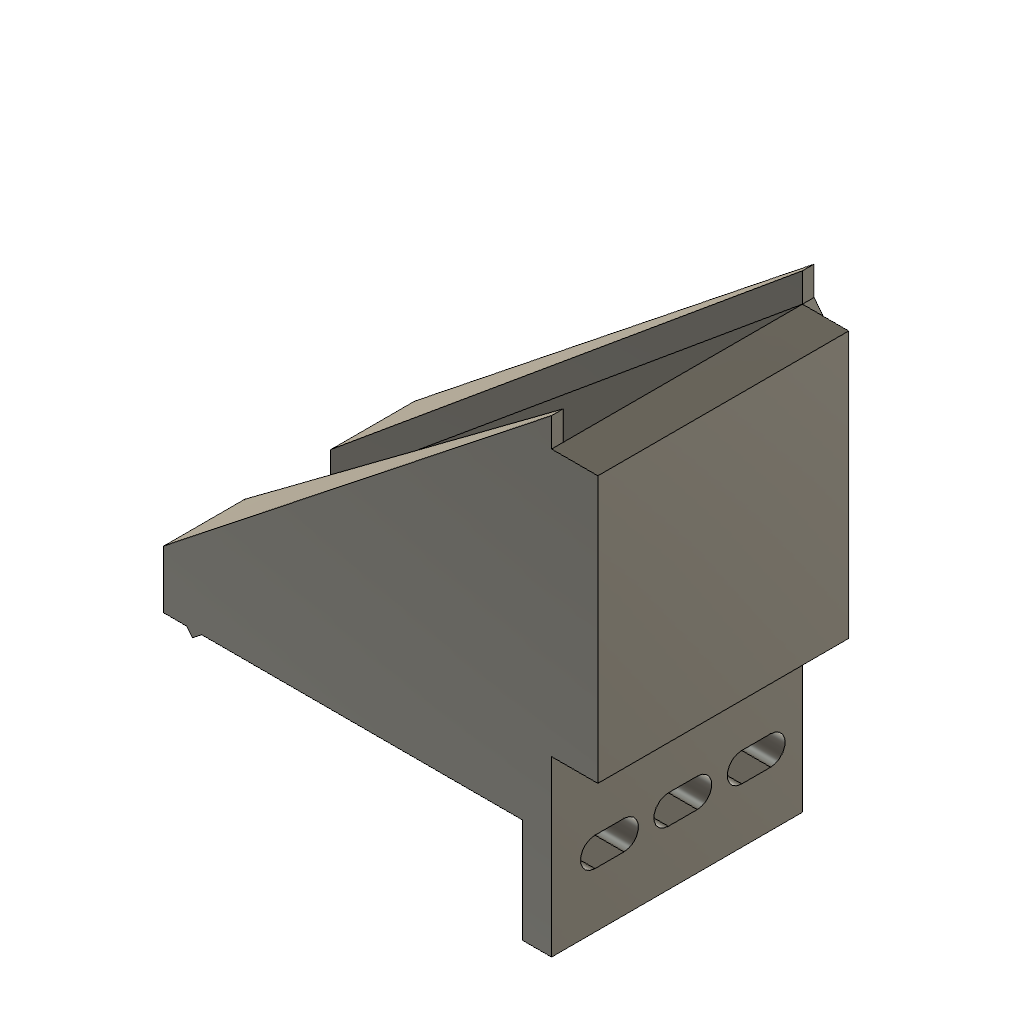
Connector - conv belt to chamber (Autodesk Fusion 360 design; units mm, degrees)
Autodesk Fusion 360 part; units mm, degrees
sketch "Sketch1" plane through (0, 0, 0) normal (1, 0, 0) x (0, 1, 0)
  line L0 (25, -15) -> (-25, -15)
  line L1 (-25, -15) -> (-25, 15)
  line L2 (-25, 15) -> (25, 15)
  line L3 (25, -15) -> (-25, 15) construction
  line L4 (-25, -15) -> (25, 15) construction
  circle A0 centre (-15, -3) radius 2.5
  circle A1 centre (-2.3333, -3) radius 2.5
  circle A2 centre (10.3333, -3) radius 2.5
  line L5 (12.3333, -3) -> (12.3333, -15)
  line L6 (12.3333, 15) -> (-26.6509, 15)
  line L7 (-26.6509, 15) -> (-26.6509, 21)
  line L8 (-26.6509, 21) -> (12.3333, 21)
  line L9 (12.3333, 21) -> (12.3333, 15)
  line L10 (-25, 15) -> (-25, 22)
  line L11 (-15, -3) -> (-25, -3)
  line L12 (-25, -3) -> (12.3333, -3)
  circle A3 centre (-17.5, -3) radius 2.5
  circle A4 centre (-12.5, -3) radius 2.5
  line L13 (-12.5, -3) -> (-12.5, -0.5)
  line L14 (-17.5, -3) -> (-17.5, -0.5)
  line L15 (-17.5, -0.5) -> (-12.5, -0.5)
  line L16 (-12.5, -3) -> (-12.5, -5.5)
  line L17 (-17.5, -3) -> (-17.5, -5.5)
  line L18 (-17.5, -5.5) -> (-12.5, -5.5)
  line L19 (-2.3333, -3) -> (-4.8333, -3)
  circle A5 centre (-4.8333, -3) radius 2.5
  circle A6 centre (0.1667, -3) radius 2.5
  line L20 (-4.8333, -3) -> (-4.8333, -0.5)
  line L21 (-4.8333, -0.5) -> (0.1667, -0.5)
  line L22 (-4.8333, -3) -> (-4.8333, -5.5)
  line L23 (-4.8333, -5.5) -> (0.1667, -5.5)
  circle A7 centre (7.8333, -3) radius 2.5
  circle A8 centre (12.8333, -3) radius 2.5
  line L24 (7.8333, -3) -> (7.8333, -0.5)
  line L25 (7.8333, -0.5) -> (12.8333, -0.5)
  line L26 (7.8333, -3) -> (7.8333, -5.5)
  line L27 (7.8333, -5.5) -> (12.8333, -5.5)
  line L28 (25, -15) -> (12.3333, -15)
  line L29 (12.3333, -15) -> (12.3333, 21)
  line L30 (12.3333, 21) -> (25, 21)
  line L31 (10.3333, -3) -> (18.3333, -3)
  line L32 (18.3333, -3) -> (18.3333, -17)
  line L33 (18.3333, -15) -> (18.3333, 15)
  line L34 (18.3333, 15) -> (18.3333, 21)
  dimension "d1" = 50
  dimension "d2" = 30
  dimension "d3" = 5
  dimension "d4" = 5
  dimension "d5" = 5
  dimension "d6" = 10
  dimension "d7" = 12.6667
  dimension "d8" = 12.6667
  dimension "d9" = 18
  dimension "d10" = 18
  dimension "d12" = 6
  dimension "d13" = 5
  dimension "d14" = 5
  dimension "d15" = 5
  dimension "d16" = 5
  dimension "d17" = 5
  dimension "d18" = 5
  dimension "d19" = 8
  constraint horizontal L0
  constraint perpendicular L0 L1
  constraint parallel L0 L2
  constraint coincident L3 origin
  constraint coincident L4 origin
  constraint coincident L2 L6.start
  constraint coincident L0 L5.end
  constraint perpendicular L0 L5
  constraint horizontal L6
  constraint vertical L7
  constraint horizontal L8
  constraint vertical L9
  constraint perpendicular L8 L10
  constraint coincident A0.centre L11.start
  constraint coincident L1 L11.end
  constraint perpendicular L1 L11
  constraint coincident L11 A3.centre
  constraint coincident A0 A3.centre
  constraint coincident A0 A4.centre
  constraint coincident L12 A4.centre
  constraint coincident A4.centre L13.start
  constraint coincident A4 L13.end
  constraint tangent A0 L13
  constraint perpendicular L12 L13
  constraint coincident A3.centre L14.start
  constraint coincident A3 L14.end
  constraint tangent A0 L14
  constraint perpendicular L11 L14
  constraint coincident A4 L16.end
  constraint tangent A0 L16
  constraint perpendicular L12 L16
  constraint coincident A3 L17.end
  constraint tangent A0 L17
  constraint parallel L14 L17
  constraint coincident A1.centre L19.start
  constraint coincident L12 L19.end
  constraint coincident A1 L19.end
  constraint parallel L12 L19
  constraint coincident L19.end A5.centre
  constraint coincident A1 A6.centre
  constraint coincident L12 A6.centre
  constraint coincident A5 L20.end
  constraint tangent A1 L20
  constraint perpendicular L12 L20
  constraint coincident A6 L21.end
  constraint tangent A6 L21
  constraint coincident A5 L22.end
  constraint tangent A1 L22
  constraint vertical L22
  constraint coincident A6 L23.end
  constraint tangent A6 L23
  constraint coincident A2 A7.centre
  constraint coincident L12 A7.centre
  constraint coincident L12 A8.centre
  constraint coincident A2 A8.centre
  constraint coincident A7.centre L24.start
  constraint coincident A7 L24.end
  constraint tangent A2 L24
  constraint vertical L24
  constraint coincident A8 L25.end
  constraint tangent A8 L25
  constraint coincident A7 L26.end
  constraint tangent A2 L26
  constraint perpendicular L25 L26
  constraint coincident A8 L27.end
  constraint tangent A8 L27
  constraint horizontal L28
  constraint horizontal L30
  constraint coincident A2.centre L31.start
  constraint parallel L12 L31
  constraint perpendicular L0 L32
  constraint coincident L32 L33.start
  constraint coincident L0 L33.start
  constraint coincident L2 L33.end
  constraint perpendicular L2 L33
  constraint coincident L30 L34.end
  constraint perpendicular L30 L34
  measures "d1" distance of L1.end L2.end
  measures "d2" distance of L0.end L1.end
  measures "d3" diameter of A0
  measures "d4" diameter of A1
  measures "d5" diameter of A2
  measures "d6" distance of L1 A0.centre
  measures "d7" distance of A0.centre A1.centre
  measures "d8" horizontal distance of A1.centre A2.centre
  measures "d9" distance of L2 A0.centre
  measures "d10" distance of L2 A2.centre
  measures "d12" distance of L6.start L8.end
  measures "d13" diameter of A3
  measures "d14" diameter of A4
  measures "d15" diameter of A5
  measures "d16" diameter of A6
  measures "d17" diameter of A7
  measures "d18" diameter of A8
  measures "d19" distance of A2.centre L31.end
extrude "Extrude1" add sketch "Sketch1" along normal blind 5 contours L0 L5 A8 L27 L28 L29 L31 L32 L33 | L0 L1 L5 L11 L12 A3 A4 L18 A5 A6 L23 A7 L27 L29 | L2 A8 L25 L29 L31 L33 | L1 L2 L6 L11 L12 A3 A4 L15 A5 A6 L21 A7 L25 L29 makes body 1
extrude "Extrude2" add sketch "Sketch1" along normal blind 15 contours L2 L9 L29 L30 L34 | L2 L6 L8 L9 L10 L29 bodies 1
sketch "Sketch2" plane through (0, 0, 21) normal (0, 0, 1) x (-1, 0, 0)
  line L0 (0, 25) -> (-15, 25)
  line L1 (-15, 25) -> (-15, -18.3333)
  line L2 (-15, -18.3333) -> (0, -18.3333)
  line L3 (0, 25) -> (-7, 25)
  line L4 (-7, 25) -> (-7, -27.2024)
  line L5 (-7, -27.2024) -> (0, -27.2024)
  line L6 (0, -27.2024) -> (0, 25)
  line L7 (0, -18.3333) -> (0, 25)
  dimension "d26" = 7
  constraint horizontal L3
  constraint vertical L4
  constraint horizontal L5
  constraint vertical L6
  constraint coincident L0.start L3.start
  measures "d26" distance of L0.start L3.end
sketch "Sketch4" plane through (0, 0, 0) normal (-1, 0, 0) x (0, -1, 0)
  arc A0 (17.5, -5.5) -> (17.5, -0.5) centre (17.5, -3) ccw
  line L0 (17.5, -5.5) -> (12.5, -5.5)
  arc A1 (12.5, -0.5) -> (12.5, -5.5) centre (12.5, -3) ccw
  line L1 (12.5, -0.5) -> (17.5, -0.5)
  arc A2 (4.8333, -5.5) -> (4.8333, -0.5) centre (4.8333, -3) ccw
  line L2 (4.8333, -5.5) -> (-0.1667, -5.5)
  arc A3 (-0.1667, -0.5) -> (-0.1667, -5.5) centre (-0.1667, -3) ccw
  line L3 (-0.1667, -0.5) -> (4.8333, -0.5)
  arc A4 (-7.8333, -5.5) -> (-7.8333, -0.5) centre (-7.8333, -3) ccw
  line L4 (-7.8333, -5.5) -> (-12.8333, -5.5)
  arc A5 (-12.8333, -0.5) -> (-12.8333, -5.5) centre (-12.8333, -3) ccw
  line L5 (-12.8333, -0.5) -> (-7.8333, -0.5)
  line L6 (-18.3333, -15) -> (25, -15)
  line L7 (25, -15) -> (25, 21)
  line L8 (25, 21) -> (-18.3333, 21)
  line L9 (-18.3333, 21) -> (-18.3333, -15)
  line L10 (-18.3333, 21) -> (25, 21)
  line L11 (25, 21) -> (25, 3)
  line L12 (25, 3) -> (-18.3333, 3)
  line L13 (-18.3333, 3) -> (-18.3333, 21)
  dimension "d45" = 18
  constraint horizontal L10
  constraint vertical L11
  constraint horizontal L12
  constraint vertical L13
  constraint coincident L8.end L9.start
  measures "d45" distance of L8.end L12.end
extrude "Extrude6" add sketch "Sketch4" along normal blind 62 contours L7 L8 L9 L10 L11 L12 L13 bodies 1
sketch "Sketch5" plane through (-62, 0, 0) normal (-1, 0, 0) x (0, -1, 0)
  line L0 (-18.3333, 3) -> (25, 3)
  line L1 (25, 3) -> (25, 21)
  line L2 (25, 21) -> (-18.3333, 21)
  line L3 (-18.3333, 21) -> (-18.3333, 3)
  line L4 (-18.3333, 3) -> (25, 3)
  line L5 (25, 3) -> (25, 8)
  line L6 (25, 8) -> (-18.3333, 8)
  line L7 (-18.3333, 8) -> (-18.3333, 3)
  dimension "d48" = 5
  constraint horizontal L4
  constraint vertical L5
  constraint horizontal L6
  constraint vertical L7
  constraint coincident L1 L5.end
  constraint coincident L0.start L3.end
  measures "d48" distance of L0.start L6.end
sketch "Sketch6" plane through (0, 0, 21) normal (0, 0, 1) x (-1, 0, 0)
  line L0 (0, -18.3333) -> (0, 25)
  line L1 (-15, 25) -> (-15, -18.3333)
  line L2 (-15, -18.3333) -> (0, -18.3333)
  line L3 (62, -18.3333) -> (62, 25)
  line L4 (-15, -18.3333) -> (-5, -18.3333)
  line L5 (-5, -18.3333) -> (-5, 25)
  line L6 (-5, 25) -> (-15, 25)
  line L7 (-15, 25) -> (-15, -18.3333)
  line L8 (0, 25) -> (-15, 25)
  line L9 (0, 25) -> (0, -18.3333)
  line L10 (0, -18.3333) -> (62, -18.3333)
  line L11 (62, 25) -> (0, 25)
  point P0 (-5, 25)
  constraint horizontal L4
  constraint vertical L5
  constraint horizontal L6
  constraint vertical L7
  constraint coincident P0 L5.end
  constraint coincident L1.end L2.start
extrude "Extrude7" add sketch "Sketch6" along normal blind 40 contours L1 L2 L4 L5 L6 L7 L8 bodies 1
extrude "Extrude8" cut sketch "Sketch5" against normal blind 62 contours L1 L2 L3 L6 bodies 1
sketch "Sketch7" plane through (0, -25, 0) normal (0, -1, 0) x (1, 0, 0)
  line L0 (0, 21) -> (0, 8)
  line L1 (0, 8) -> (-62, 8)
  line L2 (-62, 8) -> (-62, 3)
  line L3 (-62, 3) -> (0, 3)
  line L4 (0, 3) -> (0, -15)
  line L5 (0, -15) -> (5, -15)
  line L6 (5, -15) -> (5, 15)
  line L7 (5, 15) -> (15, 15)
  line L8 (15, 15) -> (15, 61)
  line L9 (15, 61) -> (5, 61)
  line L10 (5, 61) -> (5, 21)
  line L11 (5, 21) -> (0, 21)
  arc A0 (-62, 8) -> (5, 61) centre (-99.3985, 124.1264) ccw
  line L12 (5, 61) -> (5, 66)
  line L13 (-62, 8) -> (-62, 13)
  arc A1 (-62, 13) -> (5, 66) centre (-99.3985, 129.1264) ccw
  dimension "d55" = 5
  dimension "d56" = 5
  dimension "d57" = 122
  dimension "d58" = 122
  constraint coincident L1.end L2.start
  constraint coincident L9.end L10.start
  constraint perpendicular L9 L12
  constraint perpendicular L1 L13
  measures "d55" distance of L9.end L12.end
  measures "d56" distance of L1.end L13.end
  measures "d57" radius of A0
  measures "d58" radius of A1
extrude "Extrude9" add sketch "Sketch7" against normal up to surface (43.3333 mm away) contours L0 L1 L10 L11 A0 bodies 1
sketch "Sketch8" plane through (-62, 0, 0) normal (-1, 0, 0) x (0, -1, 0)
  line L0 (25, 8) -> (-18.3333, 8)
  line L1 (-18.3333, 8) -> (-18.3333, 3)
  line L2 (-18.3333, 3) -> (25, 3)
  line L3 (25, 3) -> (25, 8)
  line L4 (25, 8) -> (11, 8)
  line L5 (11, 8) -> (11, 13)
  line L6 (11, 13) -> (25, 13)
  line L7 (25, 13) -> (25, 8)
  point P0 (25, 8)
  dimension "d61" = 14
  dimension "d62" = 5
  constraint horizontal L4
  constraint vertical L5
  constraint horizontal L6
  constraint vertical L7
  constraint coincident P0 L0.start
  measures "d61" distance of P0 L4.end
  measures "d62" distance of P0 L6.end
sketch "Sketch9" plane through (5, 0, 0) normal (1, 0, 0) x (0, 1, 0)
  line L0 (-25, 66) -> (-25, 61)
  line L1 (-25, 61) -> (-23, 61)
  line L2 (-23, 61) -> (-23, 66)
  line L3 (-23, 66) -> (-25, 66)
  line L4 (-25, 66) -> (-23, 66)
  line L5 (-23, 66) -> (-23, 61)
  line L6 (-23, 61) -> (-25, 61)
  line L7 (-25, 61) -> (-25, 66)
  line L8 (20.3333, 61) -> (18.3333, 61)
  line L9 (18.3333, 61) -> (18.3333, 66)
  line L10 (18.3333, 66) -> (20.3333, 66)
  line L11 (20.3333, 66) -> (20.3333, 61)
  point P0 (18.3333, 61)
  dimension "d67" = 2
  dimension "d68" = 5
  constraint horizontal L4
  constraint vertical L5
  constraint horizontal L6
  constraint vertical L7
  constraint coincident L1.end L2.start
  constraint coincident L0.start L3.end
  constraint horizontal L8
  constraint vertical L9
  constraint horizontal L10
  constraint vertical L11
  constraint coincident L8.start P0
  measures "d67" distance of L8.start P0
  measures "d68" distance of L8.start L10.end
loft "Loft1" add profiles "Sketch8", "Sketch9" section 1 contours L0 L4 L5 L6 L7 section 2 contours L0 L1 L2 L3 L4 L5 L6 L7 separate body makes body 2
extrude "Extrude11" add 1 faces at (-39.6667, -19.6667, 25.6667) along direction (0.620403, 0, -0.784283) blind 8 on bodies 2 bodies 1 2
sketch "Sketch10" plane through (-62, 0, 0) normal (-1, 0, 0) x (0, -1, 0)
  line L0 (11, 8) -> (-18.3333, 8)
  line L1 (-18.3333, 8) -> (-18.3333, 3)
  line L2 (-18.3333, 3) -> (25, 3)
  line L3 (25, 3) -> (25, 13)
  line L4 (25, 13) -> (11, 13)
  line L5 (11, 13) -> (11, 8)
  line L6 (-18.3333, 8) -> (-3.8333, 8)
  line L7 (-3.8333, 8) -> (-3.8333, 13)
  line L8 (-3.8333, 13) -> (-18.3333, 13)
  line L9 (-18.3333, 13) -> (-18.3333, 8)
  dimension "d65" = 14.5
  dimension "d66" = 5
  constraint horizontal L6
  constraint vertical L7
  constraint horizontal L8
  constraint vertical L9
  constraint coincident L0.end L1.start
  measures "d65" distance of L0.end L6.end
  measures "d66" distance of L0.end L8.end
loft "Loft2" add profiles "Sketch9", "Sketch10" section 1 contours L8 L9 L10 L11 section 2 contours L0 L6 L7 L8 L9 separate body makes body 3
extrude "Extrude12" add 1 faces at (-39.6667, 13.5, 25.6667) along direction (0.620403, 0, -0.784283) blind 8 on bodies 3 bodies 1 3
extrude "Extrude13" cut 1 faces at (15, -10.5556, 45.6667) along direction (-1, 0, 0) blind 2 on bodies 1 bodies 1
